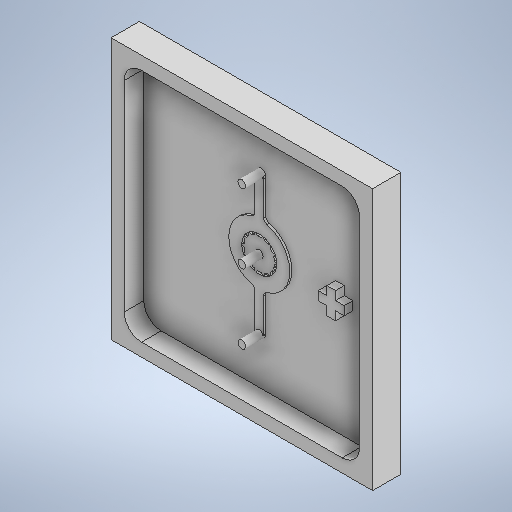
# Autodesk Inventor part: Biopsy_on_chip
Saved by Autodesk Inventor 2025.2 (Build 292293000, 293)
## iProperties
Created: 2023-10-10
Part Number: Biopsy_on_chip
Material: Generic
Document SubType Name: Modeling
Designer: giann
Density: 1 g/cm^3
Appearance: Default
Author: giann
Autodesk Inventor part; units mm, degrees
ref_plane "YZ Plane" through (0, 0, 0) normal (1, 0, 0) x (0, 1, 0)
ref_plane "XZ Plane" through (0, 0, 0) normal (0, 1, 0) x (-1, 0, 0)
ref_plane "XY Plane" through (0, 0, 0) normal (0, 0, 1) x (1, 0, 0)
sketch "Sketch1" plane through (0, 0, 0) normal (0, 0, 1) x (1, 0, 0)
  line L0 (-13.5, -13.5) -> (13.5, -13.5)
  line L1 (13.5, -13.5) -> (13.5, 13.5)
  line L2 (13.5, 13.5) -> (-13.5, 13.5)
  line L3 (-13.5, 13.5) -> (-13.5, -13.5)
  line L4 (-18.9, 0) -> (18.9, 0) construction
  line L5 (0, -18.9) -> (0, 18.9) construction
  point P0 (0, 0)
  dimension "d0" = 27
  dimension "d1" = 27
  constraints: 8 end point, 2 parallel, 1 horizontal, 1 perpendicular, 2 other
  measures "d0" distance of L1.end L2.end
  measures "d1" distance of L0.end L1.end
extrude "Extrusion1" add sketch "Sketch1" along normal blind 1
sketch "Sketch2" plane through (0, 0, 0) normal (0, 0, -1) x (-1, 0, 0)
  line L0 (-13.5, -13.5) -> (-13.5, 13.5) projected
  line L1 (13.5, -13.5) -> (-13.5, -13.5) projected
  line L2 (13.5, 13.5) -> (13.5, -13.5) projected
  line L3 (-13.5, 13.5) -> (13.5, 13.5) projected
  line L4 (15, 15) -> (-15, 15)
  line L5 (-15, 15) -> (-15, -15)
  line L6 (-15, -15) -> (15, -15)
  line L7 (15, -15) -> (15, 15)
  point P0 (0, 0)
  dimension "d4" = 1.5
  dimension "d5" = 1.5
  dimension "d6" = 1.5
  dimension "d7" = 1.5
  constraints: 8 end point, 2 parallel, 1 horizontal, 1 perpendicular
  measures "d4" distance between parallel lines of L4 L3
  measures "d5" distance between parallel lines of L5 L0
  measures "d6" distance between parallel lines of L1 L6
  measures "d7" distance between parallel lines of L2 L7
extrude "Extrusion2" add sketch "Sketch2" against normal blind 3.25
sketch "Sketch3" plane through (0, 0, 1) normal (0, 0, 1) x (1, 0, 0)
  line L0 (8.5, 1.5) -> (9.5, 1.5)
  line L1 (9.5, 1.5) -> (9.5, -1.5)
  line L2 (9.5, -1.5) -> (8.5, -1.5)
  line L3 (8.5, -1.5) -> (8.5, 1.5)
  line L4 (7.5, 0.5) -> (10.5, 0.5)
  line L5 (10.5, 0.5) -> (10.5, -0.5)
  line L6 (10.5, -0.5) -> (7.5, -0.5)
  line L7 (7.5, -0.5) -> (7.5, 0.5)
  line L8 (-18.9, 0) -> (18.9, 0) construction
  line L9 (13.5, 13.5) -> (13.5, -13.5) projected
  point P0 (0, 0)
  point P1 (8.5, -0.5)
  point P2 (9.5, -0.5)
  point P3 (9.5, 0.5)
  point P4 (8.5, 0.5)
  dimension "d10" = 1
  dimension "d11" = 3
  dimension "d12" = 1
  dimension "d13" = 1
  dimension "d14" = 3
  constraints: 16 end point, 4 parallel, 4 perpendicular, 2 horizontal, 1 other
  measures "d10" distance of L0.start L0.end
  measures "d11" distance of L5.end L6.end
  measures "d12" distance from line of L4.end L1
  measures "d13" distance between parallel lines of L2 L6
  measures "d14" distance from line of L9 L4.end
extrude "Extrusion3" add sketch "Sketch3" along normal blind 1
sketch "Sketch4" plane through (0, 0, 1) normal (0, 0, 1) x (1, 0, 0)
  circle A0 centre (0, 0) radius 2
  circle A1 centre (0, 0) radius 3.5
  line L0 (-0.5, 3.4641) -> (0.5, 3.4641)
  line L1 (0.5, 3.4641) -> (0.5, 7.9641)
  line L2 (0.5, 7.9641) -> (-0.5, 7.9641)
  line L3 (-0.5, 7.9641) -> (-0.5, 3.4641)
  line L4 (0, -18.9) -> (0, 18.9) construction
  circle A2 centre (0, 7.9641) radius 0.45
  line L5 (-18.9, 0) -> (18.9, 0) construction
  line L6 (-0.5, -3.4641) -> (0.5, -3.4641)
  line L7 (0.5, -3.4641) -> (0.5, -7.9641)
  line L8 (0.5, -7.9641) -> (-0.5, -7.9641)
  line L9 (-0.5, -7.9641) -> (-0.5, -3.4641)
  circle A3 centre (0, -7.9641) radius 0.45
  point P0 (0.45, 7.9641)
  point P1 (-0.45, 7.9641)
  point P2 (-0.45, -7.9641)
  point P3 (0.45, -7.9641)
  dimension "d17" = 4
  dimension "d18" = 1.5
  dimension "d19" = 1
  dimension "d20" = 4.5
  dimension "d21" = 0.9
  constraints: 16 end point, 5 symmetric about line, 4 centre point, 2 coincident, 2 midpoint, 2 parallel, 2 point on circle, 1 horizontal, 1 perpendicular, 1 point on line, 1 other
  measures "d17" diameter of A0
  measures "d18" radial gap between concentric circles of A1 A0
  measures "d19" distance of L1.end L2.end
  measures "d20" distance of L0.end L1.end
  measures "d21" diameter of A2
extrude "Extrusion4" add sketch "Sketch4" along normal blind 0.25 contours A0 | A1 L6 L0 | L0 A1 | A1 L3 L2 A2 L1 | L7 L8 A3 L9 A1 | A1 L6 | A2 L2 | L2 A2 | A3 L8 | L8 A3
fillet "Fillet1" radius 0.5 8 edges at (0.5, 3.4641, 1.125) (-0.5, 3.4641, 1.125) (0.5, 7.9641, 1.125) (-0.5, 7.9641, 1.125) (0.5, -3.4641, 1.125) (-0.5, -3.4641, 1.125) (0.5, -7.9641, 1.125) (-0.5, -7.9641, 1.125)
sketch "Sketch5" plane through (0, 0, 1.25) normal (0, 0, 1) x (1, 0, 0)
  circle A0 centre (0, 0) radius 2 construction
  circle A1 centre (0, 0) radius 1.75 construction
  arc A2 (0.2, 1.7385) -> (-0.2, 1.7385) centre (0, 0) ccw
  arc A3 (0.4, 1.9596) -> (-0.4, 1.9596) centre (0, 0) ccw
  line L0 (0, -21) -> (0, 21) construction
  line L1 (-0.4, 1.9596) -> (-0.2, 1.7385)
  line L2 (0.2, 1.7385) -> (0.4, 1.9596)
  arc A4 (-0.5741, 1.6531) -> (-0.9345, 1.4796) centre (0, 0) ccw
  arc A5 (-0.4898, 1.9391) -> (-1.2106, 1.592) centre (0, 0) ccw
  line L3 (-1.2106, 1.592) -> (-0.9345, 1.4796)
  line L4 (-0.5741, 1.6531) -> (-0.4898, 1.9391)
  arc A6 (-1.2345, 1.2403) -> (-1.4839, 0.9276) centre (0, 0) ccw
  arc A7 (-1.2827, 1.5345) -> (-1.7815, 0.9091) centre (0, 0) ccw
  line L5 (-1.7815, 0.9091) -> (-1.4839, 0.9276)
  line L6 (-1.2345, 1.2403) -> (-1.2827, 1.5345)
  arc A8 (-1.6504, 0.5818) -> (-1.7394, 0.1919) centre (0, 0) ccw
  arc A9 (-1.8215, 0.826) -> (-1.9995, 0.0461) centre (0, 0) ccw
  line L7 (-1.9995, 0.0461) -> (-1.7394, 0.1919)
  line L8 (-1.6504, 0.5818) -> (-1.8215, 0.826)
  arc A10 (-1.7394, -0.1919) -> (-1.6504, -0.5818) centre (0, 0) ccw
  arc A11 (-1.9995, -0.0461) -> (-1.8215, -0.826) centre (0, 0) ccw
  line L9 (-1.8215, -0.826) -> (-1.6504, -0.5818)
  line L10 (-1.7394, -0.1919) -> (-1.9995, -0.0461)
  arc A12 (-1.4839, -0.9276) -> (-1.2345, -1.2403) centre (0, 0) ccw
  arc A13 (-1.7815, -0.9091) -> (-1.2827, -1.5345) centre (0, 0) ccw
  line L11 (-1.2827, -1.5345) -> (-1.2345, -1.2403)
  line L12 (-1.4839, -0.9276) -> (-1.7815, -0.9091)
  arc A14 (-0.9345, -1.4796) -> (-0.5741, -1.6531) centre (0, 0) ccw
  arc A15 (-1.2106, -1.592) -> (-0.4898, -1.9391) centre (0, 0) ccw
  line L13 (-0.4898, -1.9391) -> (-0.5741, -1.6531)
  line L14 (-0.9345, -1.4796) -> (-1.2106, -1.592)
  arc A16 (-0.2, -1.7385) -> (0.2, -1.7385) centre (0, 0) ccw
  arc A17 (-0.4, -1.9596) -> (0.4, -1.9596) centre (0, 0) ccw
  line L15 (0.4, -1.9596) -> (0.2, -1.7385)
  line L16 (-0.2, -1.7385) -> (-0.4, -1.9596)
  arc A18 (0.5741, -1.6531) -> (0.9345, -1.4796) centre (0, 0) ccw
  arc A19 (0.4898, -1.9391) -> (1.2106, -1.592) centre (0, 0) ccw
  line L17 (1.2106, -1.592) -> (0.9345, -1.4796)
  line L18 (0.5741, -1.6531) -> (0.4898, -1.9391)
  arc A20 (1.2345, -1.2403) -> (1.4839, -0.9276) centre (0, 0) ccw
  arc A21 (1.2827, -1.5345) -> (1.7815, -0.9091) centre (0, 0) ccw
  line L19 (1.7815, -0.9091) -> (1.4839, -0.9276)
  line L20 (1.2345, -1.2403) -> (1.2827, -1.5345)
  arc A22 (1.6504, -0.5818) -> (1.7394, -0.1919) centre (0, 0) ccw
  arc A23 (1.8215, -0.826) -> (1.9995, -0.0461) centre (0, 0) ccw
  line L21 (1.9995, -0.0461) -> (1.7394, -0.1919)
  line L22 (1.6504, -0.5818) -> (1.8215, -0.826)
  arc A24 (1.7394, 0.1919) -> (1.6504, 0.5818) centre (0, 0) ccw
  arc A25 (1.9995, 0.0461) -> (1.8215, 0.826) centre (0, 0) ccw
  line L23 (1.8215, 0.826) -> (1.6504, 0.5818)
  line L24 (1.7394, 0.1919) -> (1.9995, 0.0461)
  arc A26 (1.4839, 0.9276) -> (1.2345, 1.2403) centre (0, 0) ccw
  arc A27 (1.7815, 0.9091) -> (1.2827, 1.5345) centre (0, 0) ccw
  line L25 (1.2827, 1.5345) -> (1.2345, 1.2403)
  line L26 (1.4839, 0.9276) -> (1.7815, 0.9091)
  arc A28 (0.9345, 1.4796) -> (0.5741, 1.6531) centre (0, 0) ccw
  arc A29 (1.2106, 1.592) -> (0.4898, 1.9391) centre (0, 0) ccw
  line L27 (0.4898, 1.9391) -> (0.5741, 1.6531)
  line L28 (0.9345, 1.4796) -> (1.2106, 1.592)
  point P0 (0, 2)
  point P1 (0, 1.75)
  point P2 (-0.7593, 1.5767)
  point P3 (-0.8678, 1.8019)
  point P4 (-1.3682, 1.0911)
  point P5 (-1.5637, 1.247)
  point P6 (-1.7061, 0.3894)
  point P7 (-1.9499, 0.445)
  point P8 (-1.7061, -0.3894)
  point P9 (-1.9499, -0.445)
  point P10 (-1.3682, -1.0911)
  point P11 (-1.5637, -1.247)
  point P12 (-0.7593, -1.5767)
  point P13 (-0.8678, -1.8019)
  point P14 (0, -1.75)
  point P15 (0, -2)
  point P16 (0.7593, -1.5767)
  point P17 (0.8678, -1.8019)
  point P18 (1.3682, -1.0911)
  point P19 (1.5637, -1.247)
  point P20 (1.7061, -0.3894)
  point P21 (1.9499, -0.445)
  point P22 (1.7061, 0.3894)
  point P23 (1.9499, 0.445)
  point P24 (1.3682, 1.0911)
  point P25 (1.5637, 1.247)
  point P26 (0.7593, 1.5767)
  point P27 (0.8678, 1.8019)
  dimension "d25" = 4
  dimension "d26" = 0.25
  dimension "d28" = 0.8
  dimension "d29" = 0.4
  dimension "d32" = 360
  dimension "d34" = 0.0922
  constraints: 60 point on circle, 56 end point, 29 centre point, 17 coincident, 2 point on line, 1 concentric, 172 other
  measures "d28" distance of L2.end L1.start
  measures "d29" distance of L1.end L2.start
  measures "d34" distance of L18.end L15.start
extrude "Extrusion5" cut sketch "Sketch5" against normal up to surface (0.25 mm away)
sketch "Sketch6" plane through (0, 0, 1.25) normal (0, 0, 1) x (1, 0, 0)
  arc A0 (0.45, 7.9641) -> (-0.45, 7.9641) centre (0, 7.9641) ccw projected
  arc A1 (-0.45, -7.9641) -> (0.45, -7.9641) centre (0, -7.9641) ccw projected
  circle A2 centre (0, 7.9641) radius 0.45
  circle A3 centre (0, -7.9641) radius 0.45
  point P0 (0, 0)
  point P1 (0.45, -7.9641)
  point P2 (-0.45, -7.9641)
  point P3 (-0.45, 7.9641)
  point P4 (0.45, 7.9641)
  constraints: 2 centre point, 2 coincident, 2 concentric
extrude "Extrusion6" add sketch "Sketch6" along normal up to surface (2 mm away)
sketch "Sketch11" plane through (0, 0, 1.25) normal (0, 0, 1) x (1, 0, 0)
  circle A0 centre (0, 0) radius 0.45
  circle A1 centre (0, 7.9641) radius 0.45 projected
  constraints: 1 centre point, 1 coincident, 1 equal radius
extrude "Extrusion11" add sketch "Sketch11" along normal up to surface (2 mm away) contours A0
sketch "Sketch7" plane through (0, 0, 3.25) normal (0, 0, 1) x (1, 0, 0)
  circle A0 centre (0, 7.9641) radius 0.45 projected
  circle A1 centre (0, -7.9641) radius 0.45 projected
  circle A2 centre (0, 7.9641) radius 2.25
  arc A3 (-0.45, -7.9641) -> (0.45, -7.9641) centre (0, -7.9641) ccw projected
  circle A4 centre (0, -7.9641) radius 2.25
  circle A5 centre (0, 0) radius 4.2141
  dimension "d39" = 4.5
  dimension "d40" = 4.5
  dimension "d41" = 1.5
  constraints: 3 centre point, 3 coincident
  measures "d39" diameter of A2
  measures "d40" diameter of A4
extrude "Extrusion7" add sketch "Sketch7" along normal blind 4 separate body contours A0 | A1 | A2 | A4 | A5
sketch "Sketch8" plane through (0, 0, 3.25) normal (0, 0, 1) x (1, 0, 0)
  line L0 (7.5, -0.5) -> (8.5, -0.5) projected
  line L1 (8.5, -0.5) -> (8.5, -1.5) projected
  line L2 (8.5, -1.5) -> (9.5, -1.5) projected
  line L3 (9.5, -1.5) -> (9.5, -0.5) projected
  line L4 (9.5, -0.5) -> (10.5, -0.5) projected
  line L5 (10.5, -0.5) -> (10.5, 0.5) projected
  line L6 (10.5, 0.5) -> (9.5, 0.5) projected
  line L7 (9.5, 0.5) -> (9.5, 1.5) projected
  line L8 (9.5, 1.5) -> (8.5, 1.5) projected
  line L9 (8.5, 1.5) -> (8.5, 0.5) projected
  line L10 (8.5, 0.5) -> (7.5, 0.5) projected
  line L11 (7.5, 0.5) -> (7.5, -0.5) projected
  point P0 (0, 0)
extrude "Extrusion8" add sketch "Sketch8" along normal blind 2 bodies 2
sketch "Sketch9" plane through (0, 0, 3.25) normal (0, 0, 1) x (1, 0, 0)
  line L0 (15, -15) -> (15, 15) projected
  line L1 (15, 15) -> (-15, 15) projected
  line L2 (-15, 15) -> (-15, -15) projected
  line L3 (-15, -15) -> (15, -15) projected
  line L4 (13.5, 13.5) -> (13.5, -13.5) projected
  line L5 (13.5, -13.5) -> (-13.5, -13.5) projected
  line L6 (-13.5, -13.5) -> (-13.5, 13.5) projected
  line L7 (-13.5, 13.5) -> (13.5, 13.5) projected
  point P0 (0, 0)
extrude "Extrusion9" add sketch "Sketch9" along normal up to surface (4 mm away) bodies 2
sketch "Sketch10" plane through (0, 7.9641, 3.25) normal (0, 0, -1) x (-1, 0, 0)
  line L0 (-13.5, 5.5359) -> (13.5, 5.5359) projected
  line L1 (-13.5, -21.4641) -> (-13.5, 5.5359) projected
  line L2 (13.5, -21.4641) -> (-13.5, -21.4641) projected
  line L3 (13.5, 5.5359) -> (13.5, -21.4641) projected
  line L4 (-15, 7.0359) -> (-15, -22.9641) projected
  line L5 (15, 7.0359) -> (-15, 7.0359) projected
  line L6 (15, -22.9641) -> (15, 7.0359) projected
  line L7 (-15, -22.9641) -> (15, -22.9641) projected
extrude "Extrusion10" add sketch "Sketch10" against normal blind 1 contours L0 L3 L2 L1 bodies 2
fillet "Fillet2" radius 2 4 edges at (-13.5, 13.5, 2.125) (-13.5, -13.5, 2.125) (13.5, -13.5, 2.125) (13.5, 13.5, 2.125)
equation "\"d0\" = chipLenght"
equation "\"d1\" = chipWidth"
equation "\"d4\" = moldWall"
equation "\"d5\" = moldWall"
equation "\"d6\" = moldWall"
equation "\"d7\" = moldWall"
equation "\"d17\" = diamPillar"
equation "\"d18\" = medium"
equation "\"d19\" = chanMediumW"
equation "\"d20\" = chanMedium"
equation "\"d21\" = diamInlet"
equation "\"d25\" = diamPillar"
equation "\"d26\" = trapezHeight"
equation "\"d28\" = trapezMax"
equation "\"d29\" = trapezMin"
equation "\"d39\" = reservoir"
equation "\"d40\" = reservoir"
equation "\"moldWall\" = 1.5"
equation "\"chipLenght\" = 27"
equation "\"chipWidth\" = 27"
equation "\"medium\" = 1.5"
equation "\"diamPillar\" = 4"
equation "\"chanMedium\" = 4.5"
equation "\"diamInlet\" = 0.9"
equation "\"chanMediumW\" = 1"
equation "\"trapezHeight\" = 0.25"
equation "\"trapezMax\" = 0.8"
equation "\"trapezMin\" = 0.4"
equation "\"reservoir\" = 4.5"
body "Solid1"
body "Solid2"
